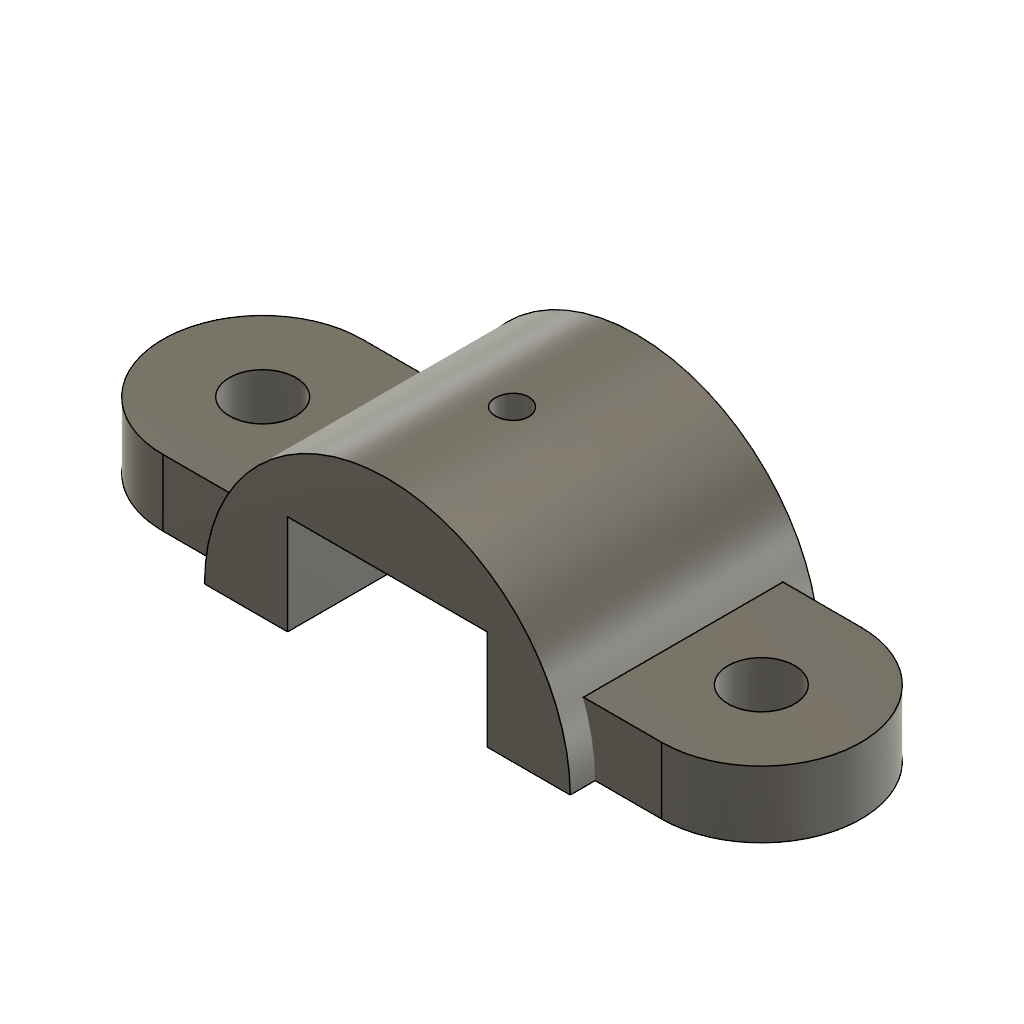
26015028 exercise3.2 (nithish R) (Autodesk Fusion 360 design; units mm, degrees)
part number: 2026-10-01-17-15-05-553
Autodesk Fusion 360 part; units mm, degrees
sketch "Sketch1" plane through (0, 0, 0) normal (0, 0, 1) x (1, 0, 0)
  line L0 (-60, 0) -> (-60, 60)
  line L1 (-60, 60) -> (60, 60)
  line L2 (60, 60) -> (60, 0)
  arc A0 (110, 0) -> (-110, 0) centre (0, 0) ccw
  line L3 (-110, 0) -> (-60, 0)
  line L4 (60, 0) -> (110, 0)
  dimension "d1" = 220
  dimension "d2" = 120
  constraint coincident A0.centre origin
  constraint perpendicular A0 L3
  constraint parallel L0 L2
  constraint collinear L3 L4
  measures "d1" diameter of A0
  measures "d2" distance of L0.end L1.end
extrude "Extrude1" add sketch "Sketch1" along normal mid plane 150 makes body 1
sketch "Sketch2" plane through (0, 0, 0) normal (0, 0, 1) x (1, 0, 0)
sketch "Sketch3" plane through (0, 0, 0) normal (0, 0, 1) x (1, 0, 0)
sketch "Sketch4" plane through (0, 0, 0) normal (0, 0, 1) x (1, 0, 0)
sketch "Sketch5" plane through (0, 0, 0) normal (0, 1, 0) x (1, 0, 0)
  circle A0 centre (0, 0) radius 10
  dimension "d6" = 20
  constraint coincident A0.centre origin
  measures "d6" diameter of A0
extrude "Extrude2" cut sketch "Sketch5" along normal blind 150 bodies 1
sketch "Sketch6" plane through (0, 0, 0) normal (0, 1, 0) x (1, 0, 0)
  line L0 (-174.1297, 0) -> (174.1297, 0)
  circle A0 centre (150, 0) radius 20
  line L1 (150, 60) -> (102, 60)
  line L2 (150, -60) -> (102, -60)
  arc A1 (150, -60) -> (150, 60) centre (150, 0) ccw
  line L3 (102, 60) -> (102, -60)
  dimension "d9" = 120
  dimension "d10" = 40
  dimension "d11" = 150
  constraint midpoint L0 origin
  constraint horizontal L0
  constraint concentric A0 A1
  constraint tangent L1 A1
  constraint horizontal L1
  constraint tangent L2 A1
  constraint horizontal L2
  constraint perpendicular L2 L3
  measures "d9" diameter of A1
  measures "d10" diameter of A0
  measures "d11" distance of origin A0.centre
extrude "Extrude3" add sketch "Sketch6" along normal blind 40 separate body makes body 2
mirror "Mirror1" about plane through (0, 0, 0) normal (1, 0, 0) of bodies 2 makes body 3
fillet "Fillet1" radius 1 1 edges at (102, 40, 0) on bodies 2
form "Form1" [no effect]
equation "d4 = ( 150 / 2 ) * 1 mm"
